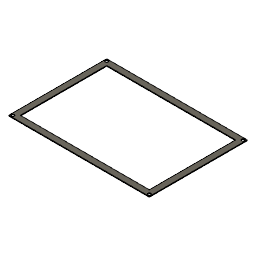
Mainboard frame bracket (Autodesk Fusion 360 design; units mm, degrees)
Autodesk Fusion 360 part; units mm, degrees
sketch "Sketch1" plane through (0, 0, 0) normal (0, 0, 1) x (1, 0, 0)
  line L0 (0, 0) -> (165, 0)
  line L1 (165, 0) -> (165, 115)
  line L2 (165, 115) -> (0, 115)
  line L3 (0, 115) -> (0, 0)
  dimension "d1" = 165
  dimension "d2" = 115
  constraint horizontal L0
  constraint vertical L1
  constraint horizontal L2
  constraint vertical L3
  constraint coincident L0.start L3.end
  measures "d1" distance of L0.start L0.end
  measures "d2" distance of L0.start L2.end
extrude "Extrude1" add sketch "Sketch1" along normal blind 1
sketch "Sketch2" plane through (0, 0, 1) normal (0, 0, 1) x (-1, 0, 0)
  line L0 (0, -115) -> (0, 0)
  line L1 (0, 0) -> (-165, 0)
  line L2 (-165, 0) -> (-165, -115)
  line L3 (-165, -115) -> (0, -115)
  line L4 (-5, -5) -> (-160, -5)
  line L5 (-160, -5) -> (-160, -110)
  line L6 (-160, -110) -> (-5, -110)
  line L7 (-5, -110) -> (-5, -5)
  line L8 (-5, -5) -> (-160, -110) construction
  line L9 (-160, -5) -> (-5, -110) construction
  point P0 (-82.5, -57.5)
  dimension "d5" = 155
  dimension "d6" = 105
  constraint horizontal L4
  constraint perpendicular L4 L5
  constraint parallel L4 L6
  constraint parallel L5 L7
  constraint coincident L8 P0
  constraint coincident L9 P0
  measures "d5" distance of L5.end L6.end
  measures "d6" distance of L4.end L5.end
sketch "Sketch3" plane through (0, 0, 1) normal (0, 0, 1) x (-1, 0, 0)
  circle A0 centre (-2.5, -2.5) radius 1.7
  circle A1 centre (-2.5, -112.5) radius 1.7
  circle A2 centre (-162.5, -112.5) radius 1.7
  circle A3 centre (-162.5, -2.5) radius 1.7
  dimension "d7" = 3.4
  dimension "d8" = 3.4
  dimension "d9" = 3.4
  dimension "d10" = 3.4
  measures "d7" diameter of A0
  measures "d8" diameter of A1
  measures "d9" diameter of A2
  measures "d10" diameter of A3
extrude "Extrude2" cut sketch "Sketch3" against normal blind 456
extrude "Extrude3" cut sketch "Sketch2" against normal blind 546 contours L4 L5 L6 L7
extrude "Extrude4" add 1 faces at (160, 40, 0.6667) along direction (-1, 0, 0) blind 2
extrude "Extrude5" add 1 faces at (5, 75, 0.6667) along direction (1, 0, 0) blind 2
extrude "Extrude6" add 1 faces at (107.6667, 110, 0.6667) along direction (0, -1, 0) blind 2
extrude "Extrude7" add 1 faces at (57.3333, 5, 0.6667) along direction (0, 1, 0) blind 2
extrude "Extrude8" cut 1 faces at (57.3004, 111.5657, 1) along direction (0, 0, -1) blind 0.2
